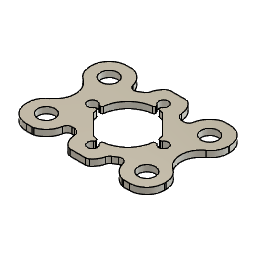
DartBox 22mm Al Mount Plate v4 (Autodesk Fusion 360 design; units mm, degrees)
Autodesk Fusion 360 part; units mm, degrees
sketch "Sketch1" plane through (0, 0, 0) normal (0, 1, 0) x (1, 0, 0)
  arc A0 (0.161767, -0.264583) -> (0.153531, -0.261707) centre (0.161767, -0.251354) cw
  arc A1 (0.153531, -0.261707) -> (0.136347, -0.227367) centre (0.181901, -0.226042) cw
  arc A2 (0.132478, -0.218398) -> (0.136347, -0.227367) centre (0.123124, -0.227752) cw
  line L0 (0.132478, -0.218398) -> (0.129622, -0.215541)
  arc A3 (0.120268, -0.211667) -> (0.129622, -0.215541) centre (0.120268, -0.224896) cw
  line L1 (0.120268, -0.211667) -> (0.113602, -0.211667)
  arc A4 (0.100529, -0.222869) -> (0.113602, -0.211667) centre (0.113602, -0.224896) cw
  arc A5 (0.100529, -0.222869) -> (0.065712, -0.263921) centre (0.049609, -0.214974) cw
  arc A6 (0.065712, -0.263921) -> (0.061578, -0.264583) centre (0.061578, -0.251354) cw
  line L2 (0.061578, -0.264583) -> (0.046302, -0.264583)
  arc A7 (0.046302, -0.264583) -> (0, -0.218281) centre (0.046302, -0.218281) cw
  line L3 (0, -0.218281) -> (0, -0.214143)
  arc A8 (0, -0.214143) -> (0.020133, -0.175946) centre (0.046302, -0.214143) cw
  arc A9 (0.020133, -0.088638) -> (0.020133, -0.175946) centre (-0.009775, -0.132292) cw
  arc A10 (0.020133, -0.088638) -> (0, -0.05044) centre (0.046302, -0.05044) cw
  line L4 (0, -0.05044) -> (0, -0.046302)
  arc A11 (0, -0.046302) -> (0.046302, 0) centre (0.046302, -0.046302) cw
  line L5 (0.046302, 0) -> (0.061578, 0)
  arc A12 (0.061578, 0) -> (0.065712, -0.000663) centre (0.061578, -0.013229) cw
  arc A13 (0.065712, -0.000663) -> (0.099607, -0.037145) centre (0.049609, -0.049609) cw
  arc A14 (0.120075, -0.044751) -> (0.099607, -0.037145) centre (0.112443, -0.033945) cw
  arc A15 (0.120075, -0.044751) -> (0.130661, -0.038163) centre (0.181901, -0.132292) cw
  arc A16 (0.137287, -0.029243) -> (0.130661, -0.038163) centre (0.124336, -0.026543) cw
  arc A17 (0.137287, -0.029243) -> (0.153531, -0.002876) centre (0.181901, -0.038542) cw
  arc A18 (0.153531, -0.002876) -> (0.161767, 0) centre (0.161767, -0.013229) cw
  line L6 (0.161767, 0) -> (0.202035, 0)
  arc A19 (0.202035, 0) -> (0.210271, -0.002876) centre (0.202035, -0.013229) cw
  arc A20 (0.210271, -0.002876) -> (0.227455, -0.037216) centre (0.181901, -0.038542) cw
  arc A21 (0.231324, -0.046186) -> (0.227455, -0.037216) centre (0.240678, -0.036831) cw
  line L7 (0.231324, -0.046186) -> (0.23418, -0.049042)
  arc A22 (0.243535, -0.052917) -> (0.23418, -0.049042) centre (0.243535, -0.039688) cw
  line L8 (0.243535, -0.052917) -> (0.250201, -0.052917)
  arc A23 (0.263274, -0.041714) -> (0.250201, -0.052917) centre (0.250201, -0.039688) cw
  arc A24 (0.263274, -0.041714) -> (0.29809, -0.000663) centre (0.314193, -0.049609) cw
  arc A25 (0.29809, -0.000663) -> (0.302224, 0) centre (0.302224, -0.013229) cw
  line L9 (0.302224, 0) -> (0.3175, 0)
  arc A26 (0.3175, 0) -> (0.363802, -0.046302) centre (0.3175, -0.046302) cw
  line L10 (0.363802, -0.046302) -> (0.363802, -0.05044)
  arc A27 (0.363802, -0.05044) -> (0.34367, -0.088638) centre (0.3175, -0.05044) cw
  arc A28 (0.34367, -0.175946) -> (0.34367, -0.088638) centre (0.373578, -0.132292) cw
  arc A29 (0.34367, -0.175946) -> (0.363802, -0.214143) centre (0.3175, -0.214143) cw
  line L11 (0.363802, -0.214143) -> (0.363802, -0.218281)
  arc A30 (0.363802, -0.218281) -> (0.3175, -0.264583) centre (0.3175, -0.218281) cw
  line L12 (0.3175, -0.264583) -> (0.302224, -0.264583)
  arc A31 (0.302224, -0.264583) -> (0.29809, -0.263921) centre (0.302224, -0.251354) cw
  arc A32 (0.29809, -0.263921) -> (0.264195, -0.227438) centre (0.314193, -0.214974) cw
  arc A33 (0.243727, -0.219832) -> (0.264195, -0.227438) centre (0.251359, -0.230638) cw
  arc A34 (0.243727, -0.219832) -> (0.233141, -0.226421) centre (0.181901, -0.132292) cw
  arc A35 (0.226515, -0.235341) -> (0.233141, -0.226421) centre (0.239466, -0.23804) cw
  arc A36 (0.226515, -0.235341) -> (0.210271, -0.261707) centre (0.181901, -0.226042) cw
  arc A37 (0.210271, -0.261707) -> (0.202035, -0.264583) centre (0.202035, -0.251354) cw
  line L13 (0.202035, -0.264583) -> (0.161767, -0.264583)
  circle A38 centre (0.049609, -0.049609) radius 0.022423
  circle A39 centre (0.049609, -0.214974) radius 0.022423
  circle A40 centre (0.314193, -0.049609) radius 0.022423
  circle A41 centre (0.314193, -0.214974) radius 0.022423
  arc A42 (0.187193, -0.209808) -> (0.190691, -0.205867) centre (0.191161, -0.209808) cw
  line L14 (0.187193, -0.209808) -> (0.187193, -0.212423)
  arc A43 (0.18893, -0.215705) -> (0.187193, -0.212423) centre (0.191161, -0.212423) cw
  arc A44 (0.18893, -0.215705) -> (0.174872, -0.215705) centre (0.181901, -0.226042) cw
  arc A45 (0.176609, -0.212423) -> (0.174872, -0.215705) centre (0.172641, -0.212423) cw
  line L15 (0.176609, -0.212423) -> (0.176609, -0.209808)
  arc A46 (0.173111, -0.205867) -> (0.176609, -0.209808) centre (0.172641, -0.209808) cw
  arc A47 (0.173111, -0.205867) -> (0.163431, -0.204052) centre (0.181901, -0.132292) cw
  line L16 (0.163431, -0.204052) -> (0.110141, -0.150761)
  arc A48 (0.110141, -0.150761) -> (0.108325, -0.141081) centre (0.181901, -0.132292) cw
  arc A49 (0.104385, -0.137583) -> (0.108325, -0.141081) centre (0.104385, -0.141552) cw
  line L17 (0.104385, -0.137583) -> (0.10177, -0.137583)
  arc A50 (0.098488, -0.13932) -> (0.10177, -0.137583) centre (0.10177, -0.141552) cw
  arc A51 (0.098488, -0.13932) -> (0.098488, -0.125263) centre (0.088151, -0.132292) cw
  arc A52 (0.10177, -0.127) -> (0.098488, -0.125263) centre (0.10177, -0.123031) cw
  line L18 (0.10177, -0.127) -> (0.104385, -0.127)
  arc A53 (0.108325, -0.123502) -> (0.104385, -0.127) centre (0.104385, -0.123031) cw
  arc A54 (0.108325, -0.123502) -> (0.173111, -0.058716) centre (0.181901, -0.132292) cw
  arc A55 (0.176609, -0.054775) -> (0.173111, -0.058716) centre (0.172641, -0.054775) cw
  line L19 (0.176609, -0.054775) -> (0.176609, -0.05216)
  arc A56 (0.174872, -0.048878) -> (0.176609, -0.05216) centre (0.172641, -0.05216) cw
  arc A57 (0.174872, -0.048878) -> (0.18893, -0.048878) centre (0.181901, -0.038542) cw
  arc A58 (0.187193, -0.05216) -> (0.18893, -0.048878) centre (0.191161, -0.05216) cw
  line L20 (0.187193, -0.05216) -> (0.187193, -0.054775)
  arc A59 (0.190691, -0.058716) -> (0.187193, -0.054775) centre (0.191161, -0.054775) cw
  arc A60 (0.190691, -0.058716) -> (0.200371, -0.060531) centre (0.181901, -0.132292) cw
  line L21 (0.200371, -0.060531) -> (0.253661, -0.113822)
  arc A61 (0.253661, -0.113822) -> (0.255477, -0.123502) centre (0.181901, -0.132292) cw
  arc A62 (0.259418, -0.127) -> (0.255477, -0.123502) centre (0.259418, -0.123031) cw
  line L22 (0.259418, -0.127) -> (0.262033, -0.127)
  arc A63 (0.265314, -0.125263) -> (0.262033, -0.127) centre (0.262033, -0.123031) cw
  arc A64 (0.265314, -0.125263) -> (0.265314, -0.13932) centre (0.275651, -0.132292) cw
  arc A65 (0.262033, -0.137583) -> (0.265314, -0.13932) centre (0.262033, -0.141552) cw
  line L23 (0.262033, -0.137583) -> (0.259418, -0.137583)
  arc A66 (0.255477, -0.141081) -> (0.259418, -0.137583) centre (0.259418, -0.141552) cw
  arc A67 (0.255477, -0.141081) -> (0.190691, -0.205867) centre (0.181901, -0.132292) cw
  point P0 (0.072033, -0.049609)
  point P1 (0.072033, -0.214974)
  point P2 (0.336616, -0.049609)
  point P3 (0.336616, -0.214974)
extrude "Extrude1" add sketch "Sketch1" along normal blind 1.5875 contours A0 A1 A2 L0 A3 L1 A4 A5 A6 L2 A7 L3 A8 A9 A10 L4 A11 L5 A12 A13 A14 A15 A16 A17 A18 L6 A19 A20 A21 L7 A22 L8 A23 A24 A25 L9 A26 L10 A27 A28 A29 L11 A30 L12 A31 A32 A33 A34 A35 A36 A37 L13 picked at (0.095474, -0.188649)
scale "Scale1" factor 96 about (0.153531, 1.5875, 0.002876) bodies 1
sketch "Sketch2" plane through (0, 1.5875, 0) normal (0, 1, 0) x (-1, 0, 0)
  circle A0 centre (-15.57703, 4.489289) radius 2.15265
  circle A1 centre (9.82297, 20.364289) radius 2.15265
  circle A2 centre (9.82297, 4.489289) radius 2.15265
  arc A3 (-10.884711, 13.101551) -> (-10.56965, 12.934788) centre (-10.56965, 13.315788) ccw
  line L0 (-10.56965, 12.934788) -> (-10.318616, 12.934788)
  arc A4 (-10.318616, 12.934788) -> (-9.940307, 13.270594) centre (-10.318617, 13.315788) ccw
  arc A5 (-3.720836, 19.490065) -> (-9.940307, 13.270594) centre (-2.87703, 12.426789) ccw
  arc A6 (-3.720836, 19.490065) -> (-3.385028, 19.868375) centre (-3.766029, 19.868376) ccw
  line L1 (-3.385029, 19.868375) -> (-3.385029, 20.11941)
  arc A7 (-3.385029, 20.11941) -> (-3.551792, 20.434471) centre (-3.766029, 20.119411) ccw
  arc A8 (-2.202267, 20.43447) -> (-3.551792, 20.434471) centre (-2.877029, 21.426788) ccw
  arc A9 (-2.202267, 20.43447) -> (-2.369029, 20.119409) centre (-1.98803, 20.119411) ccw
  line L2 (-2.36903, 20.119409) -> (-2.36903, 19.868375)
  arc A10 (-2.36903, 19.868375) -> (-2.033224, 19.490066) centre (-1.98803, 19.868376) ccw
  arc A11 (-1.103948, 19.315771) -> (-2.033224, 19.490066) centre (-2.87703, 12.426789) ccw
  line L3 (-1.103948, 19.315771) -> (4.011953, 14.199864)
  arc A12 (4.186246, 13.270597) -> (4.011953, 14.199864) centre (-2.87703, 12.426789) ccw
  arc A13 (4.186246, 13.270597) -> (4.564557, 12.934788) centre (4.564557, 13.315788) ccw
  line L4 (4.564557, 12.934788) -> (4.815591, 12.934788)
  arc A14 (4.815591, 12.934788) -> (5.130652, 13.101551) centre (4.815591, 13.315788) ccw
  arc A15 (5.130652, 11.752026) -> (5.130652, 13.101551) centre (6.12297, 12.426788) ccw
  arc A16 (5.130652, 11.752026) -> (4.815591, 11.918789) centre (4.815591, 11.537789) ccw
  line L5 (4.815591, 11.918789) -> (4.564557, 11.918789)
  arc A17 (4.564557, 11.918789) -> (4.186247, 11.582983) centre (4.564557, 11.537789) ccw
  arc A18 (-2.033224, 5.363512) -> (4.186247, 11.582983) centre (-2.87703, 12.426789) ccw
  arc A19 (-2.033224, 5.363512) -> (-2.369029, 4.985202) centre (-1.98803, 4.985202) ccw
  line L6 (-2.36903, 4.985202) -> (-2.36903, 4.734168)
  arc A20 (-2.36903, 4.734168) -> (-2.202268, 4.419107) centre (-1.98803, 4.734168) ccw
  arc A21 (-3.55179, 4.419107) -> (-2.202268, 4.419107) centre (-2.877029, 3.42679) ccw
  arc A22 (-3.55179, 4.419107) -> (-3.385028, 4.734168) centre (-3.766029, 4.734168) ccw
  line L7 (-3.385029, 4.734168) -> (-3.385029, 4.985202)
  arc A23 (-3.385029, 4.985202) -> (-3.720835, 5.363512) centre (-3.766029, 4.985202) ccw
  arc A24 (-4.650105, 5.537806) -> (-3.720835, 5.363512) centre (-2.87703, 12.426789) ccw
  line L8 (-4.650105, 5.537806) -> (-9.766013, 10.653714)
  arc A25 (-9.940305, 11.582975) -> (-9.766013, 10.653714) centre (-2.87703, 12.426789) ccw
  arc A26 (-9.940305, 11.582975) -> (-10.318616, 11.918789) centre (-10.318617, 11.537789) ccw
  line L9 (-10.318616, 11.918789) -> (-10.569651, 11.918789)
  arc A27 (-10.569651, 11.918789) -> (-10.884711, 11.752026) centre (-10.56965, 11.537789) ccw
  arc A28 (-10.884711, 13.101551) -> (-10.884711, 11.752026) centre (-11.877029, 12.426788) ccw
  circle A29 centre (-15.57703, 20.364289) radius 2.15265
  arc A30 (-7.79607, 21.463175) -> (-7.159988, 22.319481) centre (-8.40327, 22.578616) ccw
  arc A31 (-7.79607, 21.463175) -> (-8.812345, 20.830673) centre (-2.87703, 12.426789) ccw
  arc A32 (-10.777277, 21.560838) -> (-8.812344, 20.830673) centre (-9.544992, 21.868039) ccw
  arc A33 (-10.777277, 21.560838) -> (-14.031139, 25.063178) centre (-15.577029, 20.364288) ccw
  arc A34 (-14.031139, 25.063178) -> (-14.428029, 25.126789) centre (-14.428033, 23.856789) ccw
  line L10 (-14.428029, 25.126789) -> (-15.894531, 25.126789)
  arc A35 (-15.894531, 25.126789) -> (-20.33953, 20.681789) centre (-15.89453, 20.681789) ccw
  line L11 (-20.33953, 20.681789) -> (-20.33953, 20.284532)
  arc A36 (-20.33953, 20.284532) -> (-18.406805, 16.617585) centre (-15.89453, 20.284532) ccw
  arc A37 (-18.406805, 8.235992) -> (-18.406805, 16.617585) centre (-21.277976, 12.426788) ccw
  arc A38 (-18.406805, 8.235992) -> (-20.33953, 4.569045) centre (-15.89453, 4.569045) ccw
  line L12 (-20.33953, 4.569045) -> (-20.33953, 4.171789)
  arc A39 (-20.33953, 4.171789) -> (-15.894531, -0.273211) centre (-15.89453, 4.171789) ccw
  line L13 (-15.894531, -0.273211) -> (-14.428029, -0.273211)
  arc A40 (-14.428029, -0.273211) -> (-14.031139, -0.209601) centre (-14.42803, 0.996789) ccw
  arc A41 (-14.031139, -0.209601) -> (-10.688788, 3.731375) centre (-15.57703, 4.489288) ccw
  arc A42 (-9.433783, 4.806789) -> (-10.688788, 3.731375) centre (-9.433783, 3.536789) ccw
  line L14 (-9.433783, 4.806789) -> (-8.793845, 4.806789)
  arc A43 (-7.89582, 4.434814) -> (-8.793845, 4.806789) centre (-8.793846, 3.536789) ccw
  line L15 (-7.89582, 4.434814) -> (-7.621615, 4.16061)
  arc A44 (-7.250179, 3.299526) -> (-7.621615, 4.16061) centre (-8.519642, 3.262585) ccw
  arc A45 (-7.250179, 3.299526) -> (-5.600528, 0.002875) centre (-2.877029, 3.42679) ccw
  arc A46 (-5.600528, 0.002876) -> (-4.809936, -0.273211) centre (-4.809935, 0.996789) ccw
  line L16 (-4.809936, -0.273211) -> (-0.944123, -0.273211)
  arc A47 (-0.944123, -0.273211) -> (-0.153531, 0.002876) centre (-0.944124, 0.996789) ccw
  arc A48 (-0.153531, 0.002876) -> (1.405929, 2.534097) centre (-2.877029, 3.42679) ccw
  arc A49 (2.042009, 3.390402) -> (1.405929, 2.534097) centre (2.64921, 2.274962) ccw
  arc A50 (2.042009, 3.390402) -> (3.058285, 4.022905) centre (-2.87703, 12.426789) ccw
  arc A51 (5.023219, 3.29274) -> (3.058285, 4.022905) centre (3.790933, 2.985539) ccw
  arc A52 (5.023219, 3.29274) -> (8.27708, -0.209601) centre (9.82297, 4.489289) ccw
  arc A53 (8.27708, -0.209601) -> (8.673971, -0.273211) centre (8.673971, 0.996789) ccw
  line L17 (8.673971, -0.273211) -> (10.14047, -0.273211)
  arc A54 (10.14047, -0.273211) -> (14.58547, 4.171789) centre (10.14047, 4.171789) ccw
  line L18 (14.58547, 4.171789) -> (14.58547, 4.569045)
  arc A55 (14.58547, 4.569045) -> (12.652745, 8.235992) centre (10.14047, 4.569045) ccw
  arc A56 (12.652745, 16.617585) -> (12.652745, 8.235992) centre (15.523916, 12.426788) ccw
  arc A57 (12.652745, 16.617585) -> (14.58547, 20.284532) centre (10.14047, 20.284532) ccw
  line L19 (14.58547, 20.284532) -> (14.58547, 20.681789)
  arc A58 (14.58547, 20.681789) -> (10.14047, 25.126789) centre (10.14047, 20.681789) ccw
  line L20 (10.14047, 25.126789) -> (8.673971, 25.126789)
  arc A59 (8.673971, 25.126789) -> (8.27708, 25.063178) centre (8.673974, 23.856789) ccw
  arc A60 (8.27708, 25.063178) -> (4.934728, 21.122202) centre (9.82297, 20.364288) ccw
  arc A61 (3.679723, 20.046789) -> (4.934728, 21.122202) centre (3.679724, 21.316789) ccw
  line L21 (3.679723, 20.046789) -> (3.039786, 20.046789)
  arc A62 (2.141761, 20.418763) -> (3.039786, 20.046789) centre (3.039785, 21.316789) ccw
  line L22 (2.141761, 20.418763) -> (1.867556, 20.692968)
  arc A63 (1.49612, 21.554051) -> (1.867556, 20.692968) centre (2.765582, 21.590992) ccw
  arc A64 (1.49612, 21.554051) -> (-0.153531, 24.850702) centre (-2.877029, 21.426788) ccw
  arc A65 (-0.153531, 24.850702) -> (-0.944123, 25.126789) centre (-0.944124, 23.856789) ccw
  line L23 (-0.944123, 25.126789) -> (-4.809936, 25.126789)
  arc A66 (-4.809936, 25.126789) -> (-5.600527, 24.850703) centre (-4.809935, 23.856789) ccw
  arc A67 (-5.600527, 24.850704) -> (-7.159988, 22.319481) centre (-2.877029, 21.426788) ccw
  dimension "d4" = 25.4
sketch "Sketch3" plane through (0, 1.5875, 0) normal (0, 1, 0) x (-1, 0, 0)
  circle A0 centre (9.82297, 4.489289) radius 2.15265
  circle A1 centre (-15.57703, 4.489289) radius 2.15265
  circle A2 centre (-15.57703, 4.489289) radius 2.15265
  circle A3 centre (9.82297, 20.364289) radius 2.15265
  circle A4 centre (9.82297, 4.489289) radius 2.15265
  arc A5 (-10.884711, 13.101551) -> (-10.56965, 12.934788) centre (-10.56965, 13.315788) ccw
  line L0 (-10.56965, 12.934788) -> (-10.318616, 12.934788)
  arc A6 (-10.318616, 12.934788) -> (-9.940307, 13.270594) centre (-10.318617, 13.315788) ccw
  arc A7 (-3.720836, 19.490065) -> (-9.940307, 13.270594) centre (-2.87703, 12.426789) ccw
  arc A8 (-3.720836, 19.490065) -> (-3.385028, 19.868375) centre (-3.766029, 19.868376) ccw
  line L1 (-3.385029, 19.868375) -> (-3.385029, 20.11941)
  arc A9 (-3.385029, 20.11941) -> (-3.551792, 20.434471) centre (-3.766029, 20.119411) ccw
  arc A10 (-2.202267, 20.43447) -> (-3.551792, 20.434471) centre (-2.877029, 21.426788) ccw
  arc A11 (-2.202267, 20.43447) -> (-2.369029, 20.119409) centre (-1.98803, 20.119411) ccw
  line L2 (-2.36903, 20.119409) -> (-2.36903, 19.868375)
  arc A12 (-2.36903, 19.868375) -> (-2.033224, 19.490066) centre (-1.98803, 19.868376) ccw
  arc A13 (-1.103948, 19.315771) -> (-2.033224, 19.490066) centre (-2.87703, 12.426789) ccw
  line L3 (-1.103948, 19.315771) -> (4.011953, 14.199864)
  arc A14 (4.186246, 13.270597) -> (4.011953, 14.199864) centre (-2.87703, 12.426789) ccw
  arc A15 (4.186246, 13.270597) -> (4.564557, 12.934788) centre (4.564557, 13.315788) ccw
  line L4 (4.564557, 12.934788) -> (4.815591, 12.934788)
  arc A16 (4.815591, 12.934788) -> (5.130652, 13.101551) centre (4.815591, 13.315788) ccw
  arc A17 (5.130652, 11.752026) -> (5.130652, 13.101551) centre (6.12297, 12.426788) ccw
  arc A18 (5.130652, 11.752026) -> (4.815591, 11.918789) centre (4.815591, 11.537789) ccw
  line L5 (4.815591, 11.918789) -> (4.564557, 11.918789)
  arc A19 (4.564557, 11.918789) -> (4.186247, 11.582983) centre (4.564557, 11.537789) ccw
  arc A20 (-2.033224, 5.363512) -> (4.186247, 11.582983) centre (-2.87703, 12.426789) ccw
  arc A21 (-2.033224, 5.363512) -> (-2.369029, 4.985202) centre (-1.98803, 4.985202) ccw
  line L6 (-2.36903, 4.985202) -> (-2.36903, 4.734168)
  arc A22 (-2.36903, 4.734168) -> (-2.202268, 4.419107) centre (-1.98803, 4.734168) ccw
  arc A23 (-3.55179, 4.419107) -> (-2.202268, 4.419107) centre (-2.877029, 3.42679) ccw
  arc A24 (-3.55179, 4.419107) -> (-3.385028, 4.734168) centre (-3.766029, 4.734168) ccw
  line L7 (-3.385029, 4.734168) -> (-3.385029, 4.985202)
  arc A25 (-3.385029, 4.985202) -> (-3.720835, 5.363512) centre (-3.766029, 4.985202) ccw
  arc A26 (-4.650105, 5.537806) -> (-3.720835, 5.363512) centre (-2.87703, 12.426789) ccw
  line L8 (-4.650105, 5.537806) -> (-9.766013, 10.653714)
  arc A27 (-9.940305, 11.582975) -> (-9.766013, 10.653714) centre (-2.87703, 12.426789) ccw
  arc A28 (-9.940305, 11.582975) -> (-10.318616, 11.918789) centre (-10.318617, 11.537789) ccw
  line L9 (-10.318616, 11.918789) -> (-10.569651, 11.918789)
  arc A29 (-10.569651, 11.918789) -> (-10.884711, 11.752026) centre (-10.56965, 11.537789) ccw
  arc A30 (-10.884711, 13.101551) -> (-10.884711, 11.752026) centre (-11.877029, 12.426788) ccw
  circle A31 centre (-15.57703, 20.364289) radius 2.15265
  arc A32 (-7.79607, 21.463175) -> (-7.159988, 22.319481) centre (-8.40327, 22.578616) ccw
  arc A33 (-7.79607, 21.463175) -> (-8.812345, 20.830673) centre (-2.87703, 12.426789) ccw
  arc A34 (-10.777277, 21.560838) -> (-8.812344, 20.830673) centre (-9.544992, 21.868039) ccw
  arc A35 (-10.777277, 21.560838) -> (-14.031139, 25.063178) centre (-15.577029, 20.364288) ccw
  arc A36 (-14.031139, 25.063178) -> (-14.428029, 25.126789) centre (-14.428033, 23.856789) ccw
  line L10 (-14.428029, 25.126789) -> (-15.894531, 25.126789)
  arc A37 (-15.894531, 25.126789) -> (-20.33953, 20.681789) centre (-15.89453, 20.681789) ccw
  line L11 (-20.33953, 20.681789) -> (-20.33953, 20.284532)
  arc A38 (-20.33953, 20.284532) -> (-18.406805, 16.617585) centre (-15.89453, 20.284532) ccw
  arc A39 (-18.406805, 8.235992) -> (-18.406805, 16.617585) centre (-21.277976, 12.426788) ccw
  arc A40 (-18.406805, 8.235992) -> (-20.33953, 4.569045) centre (-15.89453, 4.569045) ccw
  line L12 (-20.33953, 4.569045) -> (-20.33953, 4.171789)
  arc A41 (-20.33953, 4.171789) -> (-15.894531, -0.273211) centre (-15.89453, 4.171789) ccw
  line L13 (-15.894531, -0.273211) -> (-14.428029, -0.273211)
  arc A42 (-14.428029, -0.273211) -> (-14.031139, -0.209601) centre (-14.42803, 0.996789) ccw
  arc A43 (-14.031139, -0.209601) -> (-10.688788, 3.731375) centre (-15.57703, 4.489288) ccw
  arc A44 (-9.433783, 4.806789) -> (-10.688788, 3.731375) centre (-9.433783, 3.536789) ccw
  line L14 (-9.433783, 4.806789) -> (-8.793845, 4.806789)
  arc A45 (-7.89582, 4.434814) -> (-8.793845, 4.806789) centre (-8.793846, 3.536789) ccw
  line L15 (-7.89582, 4.434814) -> (-7.621615, 4.16061)
  arc A46 (-7.250179, 3.299526) -> (-7.621615, 4.16061) centre (-8.519642, 3.262585) ccw
  arc A47 (-7.250179, 3.299526) -> (-5.600528, 0.002875) centre (-2.877029, 3.42679) ccw
  arc A48 (-5.600528, 0.002876) -> (-4.809936, -0.273211) centre (-4.809935, 0.996789) ccw
  line L16 (-4.809936, -0.273211) -> (-0.944123, -0.273211)
  arc A49 (-0.944123, -0.273211) -> (-0.153531, 0.002876) centre (-0.944124, 0.996789) ccw
  arc A50 (-0.153531, 0.002876) -> (1.405929, 2.534097) centre (-2.877029, 3.42679) ccw
  arc A51 (2.042009, 3.390402) -> (1.405929, 2.534097) centre (2.64921, 2.274962) ccw
  arc A52 (2.042009, 3.390402) -> (3.058285, 4.022905) centre (-2.87703, 12.426789) ccw
  arc A53 (5.023219, 3.29274) -> (3.058285, 4.022905) centre (3.790933, 2.985539) ccw
  arc A54 (5.023219, 3.29274) -> (8.27708, -0.209601) centre (9.82297, 4.489289) ccw
  arc A55 (8.27708, -0.209601) -> (8.673971, -0.273211) centre (8.673971, 0.996789) ccw
  line L17 (8.673971, -0.273211) -> (10.14047, -0.273211)
  arc A56 (10.14047, -0.273211) -> (14.58547, 4.171789) centre (10.14047, 4.171789) ccw
  line L18 (14.58547, 4.171789) -> (14.58547, 4.569045)
  arc A57 (14.58547, 4.569045) -> (12.652745, 8.235992) centre (10.14047, 4.569045) ccw
  arc A58 (12.652745, 16.617585) -> (12.652745, 8.235992) centre (15.523916, 12.426788) ccw
  arc A59 (12.652745, 16.617585) -> (14.58547, 20.284532) centre (10.14047, 20.284532) ccw
  line L19 (14.58547, 20.284532) -> (14.58547, 20.681789)
  arc A60 (14.58547, 20.681789) -> (10.14047, 25.126789) centre (10.14047, 20.681789) ccw
  line L20 (10.14047, 25.126789) -> (8.673971, 25.126789)
  arc A61 (8.673971, 25.126789) -> (8.27708, 25.063178) centre (8.673974, 23.856789) ccw
  arc A62 (8.27708, 25.063178) -> (4.934728, 21.122202) centre (9.82297, 20.364288) ccw
  arc A63 (3.679723, 20.046789) -> (4.934728, 21.122202) centre (3.679724, 21.316789) ccw
  line L21 (3.679723, 20.046789) -> (3.039786, 20.046789)
  arc A64 (2.141761, 20.418763) -> (3.039786, 20.046789) centre (3.039785, 21.316789) ccw
  line L22 (2.141761, 20.418763) -> (1.867556, 20.692968)
  arc A65 (1.49612, 21.554051) -> (1.867556, 20.692968) centre (2.765582, 21.590992) ccw
  arc A66 (1.49612, 21.554051) -> (-0.153531, 24.850702) centre (-2.877029, 21.426788) ccw
  arc A67 (-0.153531, 24.850702) -> (-0.944123, 25.126789) centre (-0.944124, 23.856789) ccw
  line L23 (-0.944123, 25.126789) -> (-4.809936, 25.126789)
  arc A68 (-4.809936, 25.126789) -> (-5.600527, 24.850703) centre (-4.809935, 23.856789) ccw
  arc A69 (-5.600527, 24.850704) -> (-7.159988, 22.319481) centre (-2.877029, 21.426788) ccw
  point P0 (10.14047, 4.569045)
  dimension "d5" = 25.4
  dimension "d6" = 15.874999
extrude "Extrude2" cut 1 faces at (-5.419933, -150.8125, 17.837113) along direction (0, 1, 0) up to surface (150.8125 mm away)
move_body "Move1" bodies 1 to x (1, 0, 0) y (0, 1, 0) z (0, 0, 1) at (-2.87703, -1.5875, -12.426789)
equation "d1 = 1 / 16 * 1 in"
equation "d7 = -( 1 / 16 ) * 1 in"
